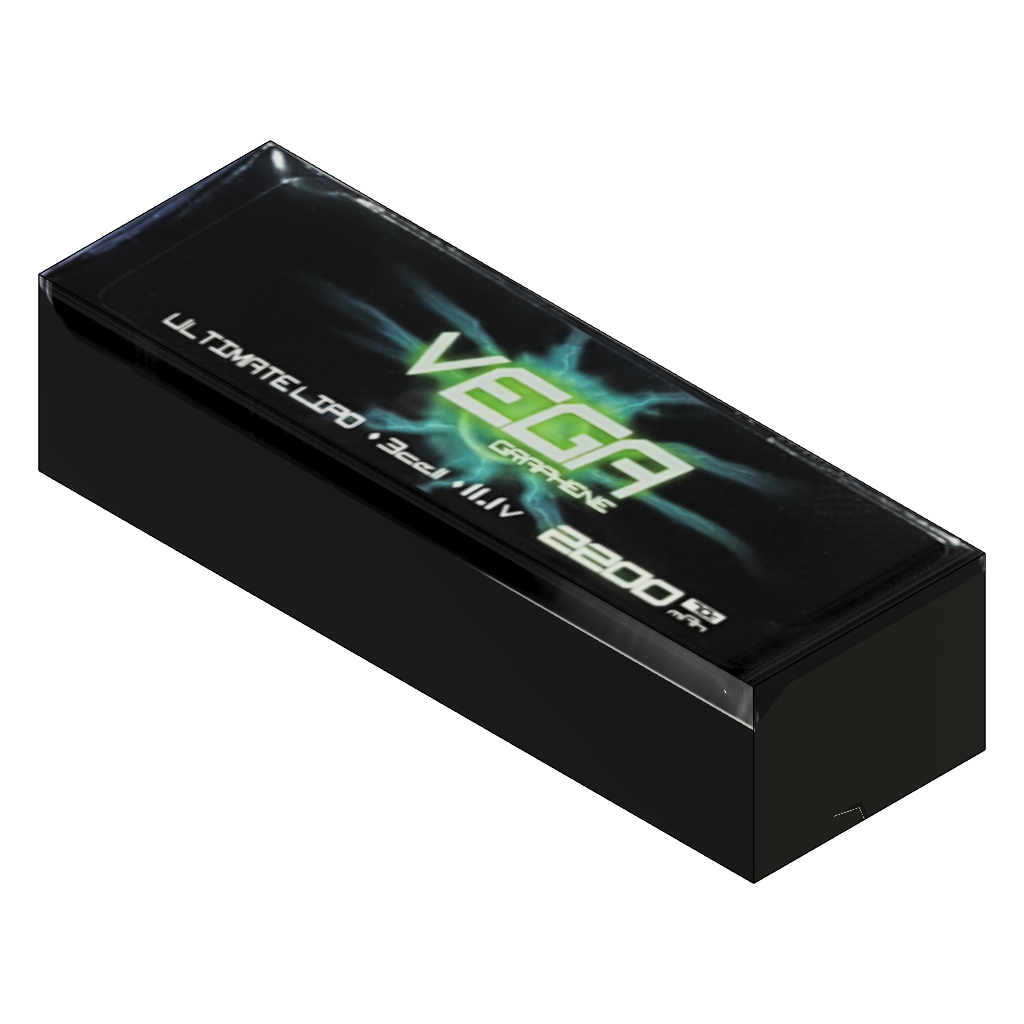
씨름 로봇 V6.2 (Autodesk Fusion 360 archive; units mm, degrees)
design "배터리"
Autodesk Fusion 360 part; units mm, degrees
sketch "스케치1" plane through (0, 0, 0) normal (0, 0, 1) x (1, 0, 0)
  line L0 (0, 0) -> (105, 0)
  line L1 (105, 0) -> (105, 34)
  line L2 (105, 34) -> (0, 34)
  line L3 (0, 34) -> (0, 0)
  dimension "d1" = 105
  dimension "d2" = 34
  constraint horizontal L0
  constraint vertical L1
  constraint horizontal L2
  constraint vertical L3
  constraint coincident L0.start L3.end
  measures "d1" distance of L0.start L0.end
  measures "d2" distance of L0.start L2.end
extrude "돌출1" add sketch "스케치1" along normal blind 25

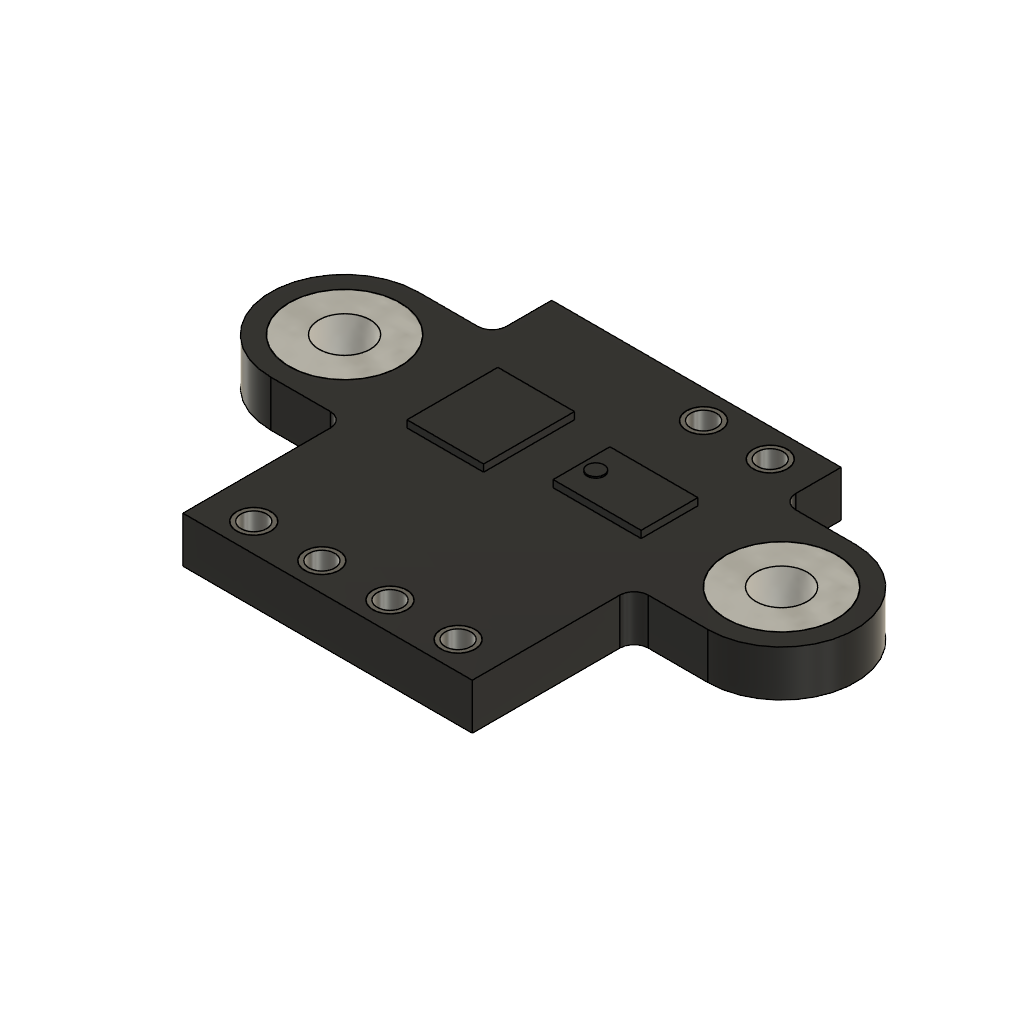
design "스펙트럼 칼라"
Autodesk Fusion 360 part; units mm, degrees
sketch "스케치1" plane through (0, 0, 0) normal (0, 0, 1) x (1, 0, 0)
  line L0 (5.2, 0) -> (15.4, 0)
  line L1 (15.4, -13) -> (5.2, -13)
  line L2 (5.2, 0) -> (15.4, 0)
  line L3 (15.4, -13) -> (5.2, -13)
  line L4 (5.2, -13) -> (5.2, -7.8)
  circle A0 centre (2.6, -4.7) radius 0.9
  circle A1 centre (18, -4.7) radius 0.9
  circle A2 centre (6.7, -12) radius 0.6
  circle A3 centre (9.1, -12) radius 0.6
  circle A4 centre (13.9, -12) radius 0.6
  circle A5 centre (11.5, -12) radius 0.6
  line L5 (10.95, -3.7) -> (14.05, -3.7)
  line L6 (14.05, -3.7) -> (14.05, -5.7)
  line L7 (14.05, -5.7) -> (10.95, -5.7)
  line L8 (10.95, -5.7) -> (10.95, -3.7)
  line L9 (6.55, -3.25) -> (9.25, -3.25)
  line L10 (9.25, -3.25) -> (9.25, -6.45)
  line L11 (9.25, -6.45) -> (6.55, -6.45)
  line L12 (6.55, -6.45) -> (6.55, -3.25)
  circle A6 centre (11.45, -4.7) radius 0.3
  circle A7 centre (11.55, -1) radius 0.45
  circle A8 centre (13.9, -1) radius 0.45
  circle A9 centre (6.7, -12) radius 0.45
  circle A10 centre (9.1, -12) radius 0.45
  circle A11 centre (11.5, -12) radius 0.45
  circle A12 centre (13.9, -12) radius 0.45
  circle A13 centre (2.6, -4.7) radius 1.95
  circle A14 centre (18, -4.7) radius 1.95
  line L13 (6.9, -3.65) -> (8.9, -3.65)
  line L14 (8.9, -3.65) -> (8.9, -6.15)
  line L15 (8.9, -6.15) -> (6.9, -6.15)
  line L16 (6.9, -6.15) -> (6.9, -3.65)
  line L17 (2.6, -7.3) -> (4.7, -7.3)
  line L18 (2.6, -2.1) -> (4.7, -2.1)
  line L19 (15.9, -2.1) -> (18, -2.1)
  line L20 (15.9, -7.3) -> (18, -7.3)
  arc A15 (5.2, -7.8) -> (4.7, -7.3) centre (4.7, -7.8) ccw
  line L21 (5.2, 0) -> (5.2, -1.6)
  arc A16 (4.7, -2.1) -> (5.2, -1.6) centre (4.7, -1.6) ccw
  line L22 (15.4, 0) -> (15.4, -1.6)
  line L23 (15.4, -7.8) -> (15.4, -13)
  arc A17 (15.4, -1.6) -> (15.9, -2.1) centre (15.9, -1.6) ccw
  arc A18 (15.9, -7.3) -> (15.4, -7.8) centre (15.9, -7.8) ccw
  arc A19 (18, -7.3) -> (18, -2.1) centre (18, -4.7) ccw
  arc A20 (2.6, -2.1) -> (2.6, -7.3) centre (2.6, -4.7) ccw
  circle A21 centre (11.55, -1) radius 0.6
  circle A22 centre (13.9, -1) radius 0.6
  dimension "d3" = 10.2
  dimension "d5" = 5.2
  dimension "d6" = 5.2
  dimension "d7" = 4.7
  dimension "d8" = 4.7
  dimension "d9" = 1.8
  dimension "d10" = 1.8
  dimension "d11" = 1.2
  dimension "d12" = 1.2
  dimension "d13" = 1.2
  dimension "d14" = 1.2
  dimension "d15" = 3.1
  dimension "d16" = 2
  dimension "d17" = 2.7
  dimension "d18" = 3.2
  dimension "d19" = 0.6
  dimension "d20" = 0.9
  dimension "d21" = 0.9
  dimension "d22" = 2.4
  dimension "d26" = 1.5
  dimension "d27" = 1
  dimension "d28" = 1
  dimension "d29" = 1
  dimension "d30" = 2.4
  dimension "d31" = 1
  dimension "d32" = 2.4
  dimension "d33" = 1.5
  dimension "d34" = 0.9
  dimension "d35" = 0.9
  dimension "d36" = 0.9
  dimension "d37" = 0.9
  dimension "d40" = 0.5
  dimension "d41" = 1
  dimension "d42" = 3.25
  dimension "d43" = 1.5
  dimension "d44" = 2.35
  dimension "d45" = 1
  dimension "d46" = 1
  dimension "d47" = 3.9
  dimension "d48" = 3.9
  dimension "d49" = 3.95
  dimension "d50" = 3.95
  dimension "d51" = 2.5
  dimension "d52" = 2
  dimension "d53" = 0.35
  dimension "d54" = 0.4
  dimension "d55" = 0.5
  dimension "d56" = 0.5
  dimension "d57" = 0.5
  dimension "d58" = 1.2
  dimension "d59" = 1.2
  constraint horizontal L0
  constraint horizontal L1
  constraint horizontal L2
  constraint vertical L22
  constraint horizontal L3
  constraint vertical L4
  constraint tangent L4 A20
  constraint tangent L22 A19
  constraint concentric A0 A20
  constraint concentric A1 A19
  constraint horizontal L5
  constraint vertical L6
  constraint horizontal L7
  constraint vertical L8
  constraint horizontal L9
  constraint vertical L10
  constraint horizontal L11
  constraint vertical L12
  constraint concentric A2 A9
  constraint concentric A3 A10
  constraint concentric A5 A11
  constraint concentric A4 A12
  constraint horizontal A1.centre A6.centre
  constraint concentric A13 A20
  constraint concentric A14 A19
  constraint horizontal L13
  constraint vertical L14
  constraint horizontal L15
  constraint vertical L16
  constraint perpendicular L4 L17
  constraint perpendicular L4 L18
  constraint tangent L18 A20
  constraint tangent L17 A20
  constraint tangent L20 A19
  constraint tangent L19 A19
  constraint coincident L0.start L4
  constraint tangent L17 A15
  constraint tangent L4 A15
  constraint tangent L21 A16
  constraint tangent L18 A16
  constraint collinear L22 L23
  constraint tangent L22 A17
  constraint tangent L19 A17
  constraint tangent L20 A18
  constraint tangent L23 A18
  constraint equal A17 A18
  constraint concentric A7 A21
  constraint concentric A8 A22
  measures "d3" distance of L0.start L0.end
  measures "d5" diameter of A20
  measures "d6" diameter of A19
  measures "d7" distance of L0 A0.centre
  measures "d8" distance of L0 A1.centre
  measures "d9" diameter of A0
  measures "d10" diameter of A1
  measures "d11" diameter of A2
  measures "d12" diameter of A3
  measures "d13" diameter of A4
  measures "d14" diameter of A5
  measures "d15" distance of L5.start L5.end
  measures "d16" distance of L5.start L7.end
  measures "d17" distance of L9.start L9.end
  measures "d18" distance of L9.start L11.end
  measures "d19" diameter of A6
  measures "d20" diameter of A7
  measures "d21" diameter of A8
  measures "d22" distance of A2.centre A3.centre
  measures "d26" distance of L4 A2.centre
  measures "d27" distance of L3 A2.centre
  measures "d28" distance of L1 A3.centre
  measures "d29" distance of L1 A5.centre
  measures "d30" distance of A3.centre A5.centre
  measures "d31" distance of L1 A4.centre
  measures "d32" distance of A4.centre A5.centre
  measures "d33" distance of A4.centre L23
  measures "d34" diameter of A9
  measures "d35" diameter of A10
  measures "d36" diameter of A11
  measures "d37" diameter of A12
  measures "d40" distance of L8 A6.centre
  measures "d41" distance of L5 A6.centre
  measures "d42" distance of L0 L9
  measures "d43" distance of A8.centre L22
  measures "d44" horizontal distance of A7.centre A8.centre
  measures "d45" distance of L2 A7.centre
  measures "d46" distance of L2 A8.centre
  measures "d47" diameter of A13
  measures "d48" diameter of A14
  measures "d49" distance of A0.centre L12
  measures "d50" distance of A1.centre L6
  measures "d51" distance of L13.start L15.end
  measures "d52" distance of L13.start L13.end
  measures "d53" distance of L12 L16
  measures "d54" distance of L9 L13
  measures "d55" radius of A15
  measures "d56" radius of A16
  measures "d57" radius of A17
  measures "d58" diameter of A21
  measures "d59" diameter of A22
extrude "돌출1" add sketch "스케치1" along normal blind 1.62 contours L0 L1 L2 L3 L4 L17 L18 L19 L20 A15 L21 A16 L22 L23 A17 A18 A19 A20 makes body 1
extrude "돌출2" add sketch "스케치1" along normal blind 1.62 separate body contours A2 | A3 | A4 | A5 | A13 | A14 | A21 | A22 makes body 2 at (9.497, -11.5501, 1.08) makes body 3 at (19.9403, -4.8942, 0.54) makes body 4 at (12.147, -1.0597, 0.54) makes body 5 at (11.897, -11.5501, 1.08) makes body 6 at (7.097, -11.5501, 1.08) makes body 7 at (4.5403, -4.8942, 0.54) makes body 8 at (14.497, -1.0597, 0.54) makes body 9 at (14.297, -11.5501, 1.08)
extrude "돌출3" add sketch "스케치1" along normal blind 1.87 contours L5 L6 L7 L8 | L9 L10 L11 L12 | L13 L14 L15 L16 bodies 1
extrude "돌출4" add sketch "스케치1" along normal blind 1.92 contours A6 bodies 1
equation "d22 = 1.8 mm + 0.6 mm"
equation "d44 = 1.9 mm + 0.45 mm"
equation "d64 = 1.62 mm + 0.25 mm"
equation "d66 = 1.62 mm + 0.3 mm"

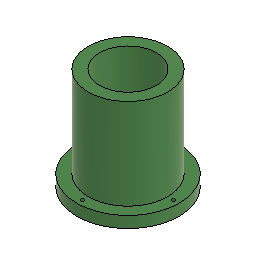
design "ColorMark"
Autodesk Fusion 360 part; units mm, degrees
sketch "스케치1" plane through (0, 0, 0) normal (0, 0, 1) x (1, 0, 0)
  circle A0 centre (0, 0) radius 45
  circle A1 centre (0, 0) radius 25
  circle A2 centre (0, 0) radius 35
  circle A3 centre (0, 0) radius 40
  line L0 (0, 0) -> (40, 0)
  circle A4 centre (40, 0) radius 1.5
  circle A5 centre (0, 40) radius 1.5
  circle A6 centre (-40, 0) radius 1.5
  circle A7 centre (0, -40) radius 1.5
  dimension "d1" = 90
  dimension "d2" = 50
  dimension "d3" = 70
  dimension "d4" = 80
  dimension "d5" = 3
  dimension "d7" = 360
  constraint coincident A0.centre A1.centre
  constraint concentric A0 A1
  constraint concentric A0 A2
  constraint concentric A1 A3
  constraint coincident A3 L0.end
  constraint horizontal L0
  constraint coincident L0.end A4.centre
  measures "d1" diameter of A0
  measures "d2" diameter of A1
  measures "d3" diameter of A2
  measures "d4" diameter of A3
  measures "d5" diameter of A4
extrude "돌출1" add sketch "스케치1" along normal blind 10 contours A0 | A2 | A3 A4 A5 A6 A7
extrude "돌출2" add sketch "스케치1" along normal blind 90 contours A2

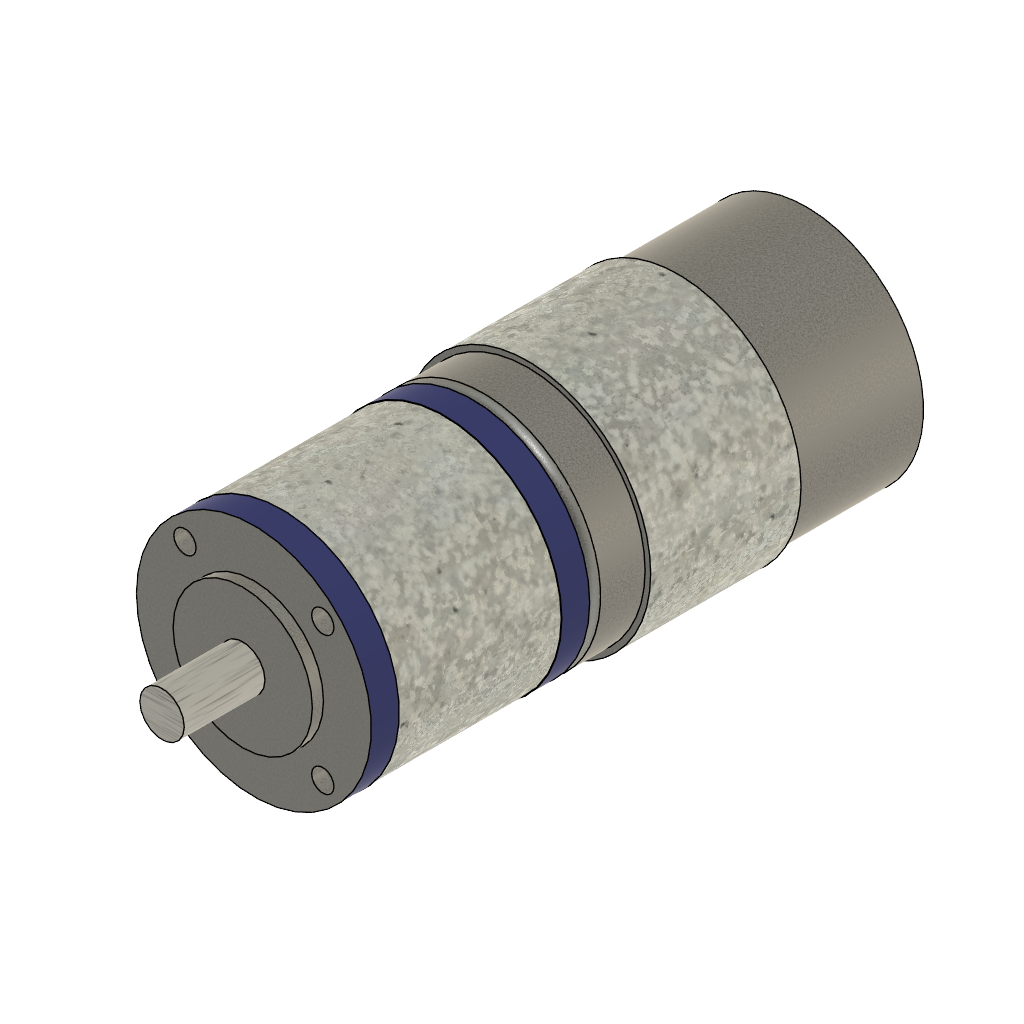
design "PG42모터"
Autodesk Fusion 360 part; units mm, degrees
sketch "스케치1" plane through (0, 0, 0) normal (0, 1, 0) x (1, 0, 0)
  circle A0 centre (0, 0) radius 21.05
  dimension "d1" = 42.1
  constraint coincident A0.centre origin
  measures "d1" diameter of A0
extrude "돌출1" add sketch "스케치1" along normal blind 60
fillet "필렛1" radius 2 1 edges at (-19.6255, 0, 7.612)
sketch "스케치2" plane through (0, 60, 0) normal (0, 1, 0) x (-1, 0, 0)
  circle A0 centre (0, 0) radius 21.05
  circle A1 centre (0, 0) radius 8.75
  dimension "d6" = 17.5
  constraint concentric A0 A1
  measures "d6" diameter of A1
extrude "돌출2" add sketch "스케치2" along normal blind 7 contours A1
sketch "스케치3" plane through (0, 67, 0) normal (0, 1, 0) x (-1, 0, 0)
  circle A0 centre (0, 0) radius 8.75
  circle A1 centre (0, 0) radius 2.5
  dimension "d9" = 5
  constraint coincident A0.centre A1.centre
  measures "d9" diameter of A1
extrude "돌출3" add sketch "스케치3" along normal blind 3 contours A1
ref_plane "작업 평면1" through (0, 10, 0) normal (0, -1, 0) x (-1, 0, 0)
sketch "스케치4" plane through (0, 10, 0) normal (0, -1, 0) x (-1, 0, 0)
  circle A0 centre (0, 0) radius 22.05
  dimension "d14" = 44.1
  constraint coincident A0.centre origin
  measures "d14" diameter of A0
extrude "돌출4" add sketch "스케치4" against normal blind 27
sketch "스케치5" plane through (0, 0, 0) normal (0, -1, 0) x (1, 0, 0)
  circle A0 centre (0, 0) radius 19.05
  circle A1 centre (0, 0) radius 21
  dimension "d17" = 42
  constraint concentric A0 A1
  measures "d17" diameter of A1
extrude "돌출5" add sketch "스케치5" along normal blind 39.2 contours A0 | A1
sketch "스케치6" plane through (0, -39.2, 0) normal (0, -1, 0) x (1, 0, 0)
  circle A0 centre (0, 0) radius 21
  circle A1 centre (0, 0) radius 17.5
  line L0 (0, 0) -> (23.0217, -23.0217)
  line L1 (0, 0) -> (32.5576, 0) construction
  circle A2 centre (12.3744, -12.3744) radius 2
  circle A3 centre (12.3744, 12.3744) radius 2
  circle A4 centre (-12.3744, 12.3744) radius 2
  circle A5 centre (-12.3744, -12.3744) radius 2
  dimension "d20" = 35
  dimension "d21" = 45
  dimension "d22" = 4
  dimension "d24" = 360
  constraint concentric A0 A1
  constraint horizontal L1
  constraint coincident A0.centre A1.centre
  constraint coincident A1 A2.centre
  constraint coincident L0 A2.centre
  measures "d20" diameter of A1
  measures "d21" angle of L0 L1
  measures "d22" diameter of A2
extrude "돌출6" cut sketch "스케치6" against normal blind 5 contours A1 A3 | A1 A3 | A1 L0 A2 | A1 L0 A2 | A1 L0 A2 | A1 L0 A2 | A1 A4 | A1 A4 | A1 A5 | A1 A5
sketch "스케치7" plane through (0, -39.2, 0) normal (0, -1, 0) x (1, 0, 0)
  circle A0 centre (12.3744, 12.3744) radius 2
  circle A1 centre (-12.3744, 12.3744) radius 2
  circle A2 centre (12.3744, -12.3744) radius 2
  circle A3 centre (-12.3744, -12.3744) radius 2
  circle A4 centre (0, 0) radius 21
  circle A5 centre (0, 0) radius 12.5
  dimension "d27" = 25
  constraint coincident A4.centre A5.centre
  measures "d27" diameter of A5
extrude "돌출7" add sketch "스케치7" along normal blind 2 contours A5
sketch "스케치8" plane through (0, -41.2, 0) normal (0, -1, 0) x (1, 0, 0)
  circle A0 centre (0, 0) radius 12.5
  circle A1 centre (0, 0) radius 4
  dimension "d30" = 8
  constraint concentric A0 A1
  measures "d30" diameter of A1
extrude "돌출8" add sketch "스케치8" along normal blind 14.5 contours A1
sketch "스케치9" plane through (0, -39.2, 0) normal (0, -1, 0) x (1, 0, 0)
  circle A0 centre (0, 0) radius 12.5
  circle A1 centre (12.3744, 12.3744) radius 2
  circle A2 centre (-12.3744, 12.3744) radius 2
  circle A3 centre (12.3744, -12.3744) radius 2
  circle A4 centre (-12.3744, -12.3744) radius 2
  circle A5 centre (0, 0) radius 21
  circle A6 centre (0, 0) radius 21.1
  dimension "d33" = 0.1
extrude "돌출9" add sketch "스케치9" against normal blind 5 contours A6
sketch "스케치10" plane through (0, 0, 0) normal (0, 1, 0) x (-1, 0, 0)
  circle A0 centre (0, 0) radius 21
  circle A1 centre (0, 0) radius 19.05
  circle A2 centre (0, 0) radius 21.1
  dimension "d36" = 0.1
extrude "돌출10" add sketch "스케치10" against normal blind 5 contours A2
equation "d14 = 42.1 mm + 2 mm"
